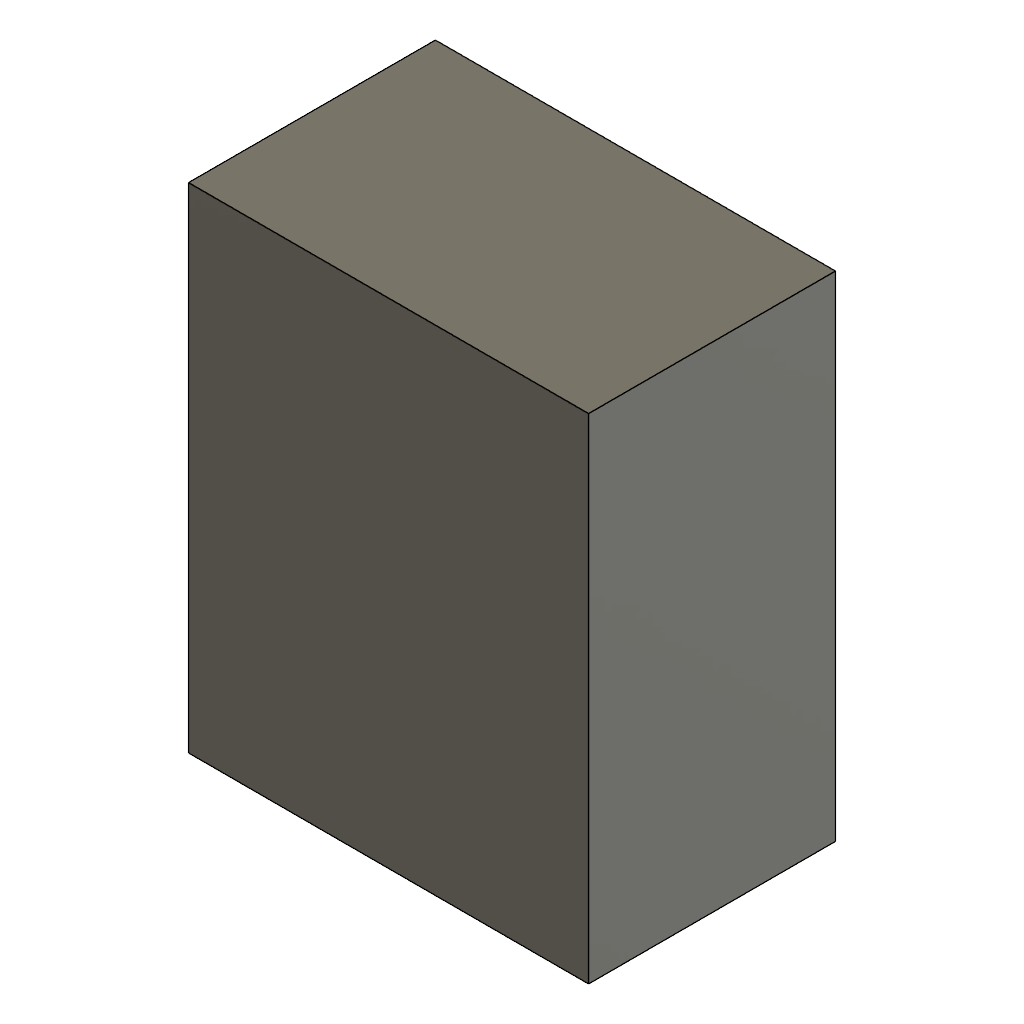
variation (Autodesk Fusion 360 design; units mm, degrees)
part number: 2026-11-23-13-10-52-668
Autodesk Fusion 360 part; units mm, degrees
sketch "Sketch1" plane through (0, 0, 0) normal (0, 0, 1) x (1, 0, 0)
  line L0 (0, 0) -> (16.2, 0)
  line L1 (16.2, 0) -> (16.2, 20)
  line L2 (16.2, 20) -> (0, 20)
  line L3 (0, 20) -> (0, 0)
extrude "ControlledBoss" add sketch "Sketch1" along normal blind 10
